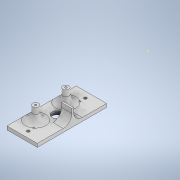
# Autodesk Inventor part: suport_steppper_part45_v2
Saved by Autodesk Inventor 2022.6 (Build 266554000, 554)
## iProperties
Created: 2026-10-28
Part Number: suport_steppper_part45_v2
Material: Generic
Document SubType Name: Modeling
Designer: Dragos Macovei
Density: 1 g/cm^3
Appearance: Default
Author: Dragos Macovei
Autodesk Inventor part; units mm, degrees
ref_plane "YZ Plane" through (0, 0, 0) normal (1, 0, 0) x (0, 1, 0)
ref_plane "XZ Plane" through (0, 0, 0) normal (0, 1, 0) x (-1, 0, 0)
ref_plane "XY Plane" through (0, 0, 0) normal (0, 0, 1) x (1, 0, 0)
sketch "Sketch1" plane through (0, 0, 0) normal (0, 1, 0) x (-1, 0, 0)
  circle A0 centre (-10.9929, 149.7887) radius 1.6
  circle A1 centre (-10.9929, 83.7887) radius 1.6
  line L0 (6.5071, 156.7887) -> (-28.4929, 156.7887)
  line L1 (-28.4929, 156.7887) -> (-28.4929, 76.7887)
  line L2 (-28.4929, 76.7887) -> (6.5071, 76.7887)
  line L3 (6.5071, 76.7887) -> (6.5071, 156.7887)
  point P0 (0, 0)
  point P1 (-10.9929, 156.7887)
  dimension "d0" = 66
  dimension "d1" = 17.5
  dimension "d2" = 35
  dimension "d3" = 17.5
  dimension "d4" = 3.2
  dimension "d5" = 3.2
  dimension "d6" = 80
  dimension "d7" = 7
  constraints: 8 end point, 2 centre point, 2 parallel, 1 horizontal, 1 midpoint, 1 perpendicular
  measures "d0" distance of A1.centre A0.centre
  measures "d1" distance from line of L3 A0.centre
  measures "d2" distance of L0.start L0.end
  measures "d3" distance from line of L3 A1.centre
  measures "d4" diameter of A0
  measures "d5" diameter of A1
  measures "d6" distance of L2.end L0.start
  measures "d7" distance of point (-10.993, 156.789) A0.centre
extrude "Extrusion1" add sketch "Sketch1" along normal blind 4
sketch "Sketch2" plane through (0, 4, 0) normal (0, 1, 0) x (1, 0, 0)
  line L0 (28.4929, -156.7887) -> (28.4929, -76.7887) projected
  line L1 (28.4929, -76.7887) -> (-6.5071, -76.7887) projected
  line L2 (-6.5071, -76.7887) -> (-6.5071, -156.7887) projected
  line L3 (-6.5071, -156.7887) -> (28.4929, -156.7887) projected
  circle A0 centre (10.9929, -149.7887) radius 1.6 projected
  circle A1 centre (10.9929, -83.7887) radius 1.6 projected
  circle A2 centre (3.9929, -134.2887) radius 1.15
  circle A3 centre (3.9929, -99.2887) radius 1.15
  line L4 (-6.5071, -76.7887) -> (-6.5071, -156.7887) projected
  line L5 (28.4929, -156.7887) -> (28.4929, -76.7887) projected
  line L6 (-6.5071, -116.7887) -> (28.4929, -116.7887)
  circle A4 centre (3.9929, -99.2887) radius 3.5
  circle A5 centre (10.9929, -149.7887) radius 1.6 projected
  line L7 (10.9929, -149.7887) -> (10.9929, -83.7887)
  circle A6 centre (3.9929, -134.2887) radius 3.5
  point P0 (0, 0)
  dimension "d10" = 35
  dimension "d11" = 17.5
  dimension "d13" = 7
  dimension "d14" = 2.3
  dimension "d15" = 2.3
  dimension "d28" = 7
  dimension "d29" = 7
  dimension "d30" = 7
  constraints: 4 centre point, 4 end point, 2 coincident, 2 midpoint, 1 perpendicular, 1 vertical
  measures "d10" distance of A2.centre A3.centre
  measures "d11" distance from line of L6 A2.centre
  measures "d13" diameter of A4
  measures "d14" diameter of A2
  measures "d15" diameter of A3
  measures "d28" distance from line of L7 A3.centre
  measures "d29" distance from line of L7 A2.centre
  measures "d30" diameter of A6
extrude "Extrusion2" add sketch "Sketch2" along normal blind 15 contours A4 | A6
fillet "Fillet1" radius 8 2 edges at (0.4929, 4, 99.2887) (0.4929, 4, 134.2887)
sketch "Sketch3" plane through (0, 4, 0) normal (0, 1, 0) x (1, 0, 0)
  line L0 (28.4929, -156.7887) -> (28.4929, -76.7887) projected
  line L1 (28.4929, -76.7887) -> (-6.5071, -76.7887) projected
  line L2 (-6.5071, -76.7887) -> (-6.5071, -94.5983) projected
  line L3 (-6.5071, -156.7887) -> (28.4929, -156.7887) projected
  circle A0 centre (10.9929, -149.7887) radius 1.6 projected
  circle A1 centre (10.9929, -83.7887) radius 1.6 projected
  arc A2 (-6.5071, -103.9791) -> (-6.5071, -94.5983) centre (3.9929, -99.2887) ccw projected
  circle A3 centre (10.9929, -116.7887) radius 5.5
  circle A4 centre (10.9929, -149.7887) radius 1.6 projected
  line L4 (10.9929, -149.7887) -> (10.9929, -83.7887)
  line L5 (-6.5071, -103.9791) -> (-6.5071, -129.5983) projected
  arc A5 (-6.5071, -138.9791) -> (-6.5071, -129.5983) centre (3.9929, -134.2887) ccw projected
  line L6 (-6.5071, -138.9791) -> (-6.5071, -156.7887) projected
  point P0 (0, 0)
  dimension "d19" = 11
  dimension "d20" = 33
  constraints: 2 end point, 1 centre point, 1 vertical
  measures "d19" diameter of A3
  measures "d20" distance of L4.end A3.centre
extrude "Extrusion3" cut sketch "Sketch3" against normal blind 15 contours L4 A3 | A3 L4
sketch "Sketch4" plane through (0, 4, 0) normal (0, 1, 0) x (1, 0, 0)
  circle A0 centre (10.9929, -116.7887) radius 5.5 projected
  line L0 (28.4929, -156.7887) -> (28.4929, -76.7887) projected
  line L1 (28.4929, -76.7887) -> (-6.5071, -76.7887) projected
  line L2 (-6.5071, -76.7887) -> (-6.5071, -94.5983) projected
  line L3 (-6.5071, -156.7887) -> (28.4929, -156.7887) projected
  circle A1 centre (10.9929, -149.7887) radius 1.6 projected
  circle A2 centre (10.9929, -83.7887) radius 1.6 projected
  arc A3 (-6.5071, -103.9791) -> (-6.5071, -94.5983) centre (3.9929, -99.2887) ccw projected
  circle A4 centre (10.9929, -116.7887) radius 5.5 projected
  line L4 (28.4929, -156.7887) -> (28.4929, -76.7887) projected
  line L5 (16.4929, -116.7887) -> (28.4929, -116.7887)
  line L6 (28.4929, -116.7887) -> (28.4929, -114.7887)
  line L7 (28.4929, -114.7887) -> (16.4929, -114.7887)
  line L8 (16.4929, -114.7887) -> (16.4929, -116.7887)
  line L9 (-6.5071, -103.9791) -> (-6.5071, -129.5983) projected
  arc A5 (-6.5071, -138.9791) -> (-6.5071, -129.5983) centre (3.9929, -134.2887) ccw projected
  line L10 (-6.5071, -138.9791) -> (-6.5071, -156.7887) projected
  point P0 (0, 0)
  dimension "d23" = 2
  constraints: 8 end point, 2 parallel, 1 horizontal, 1 horizontal alignment, 1 perpendicular, 1 point on line, 1 other
  measures "d23" distance of L6.end L5.end
extrude "Extrusion4" add sketch "Sketch4" along normal blind 15 contours L8 L7 L0 L5
fillet "Fillet2" radius 10 2 edges at (22.4929, 4, 116.7887) (22.4929, 4, 114.7887)
sketch "Sketch5" plane through (0, 4, 0) normal (0, 1, 0) x (1, 0, 0)
  point P0 (0, 0)
sketch "Sketch6" plane through (0, 4, 0) normal (0, 1, 0) x (1, 0, 0)
  line L0 (28.4929, -104.7887) -> (16.4929, -104.7887) projected
  line L1 (28.4929, -104.7887) -> (28.4929, -76.7887) projected
  line L2 (28.4929, -76.7887) -> (-6.5071, -76.7887) projected
  line L3 (-6.5071, -76.7887) -> (-6.5071, -94.5983) projected
  arc A0 (-6.5071, -103.9791) -> (-6.5071, -94.5983) centre (3.9929, -99.2887) ccw projected
  line L4 (-6.5071, -103.9791) -> (-6.5071, -129.5983) projected
  arc A1 (-6.5071, -138.9791) -> (-6.5071, -129.5983) centre (3.9929, -134.2887) ccw projected
  line L5 (-6.5071, -138.9791) -> (-6.5071, -156.7887) projected
  line L6 (-6.5071, -156.7887) -> (28.4929, -156.7887) projected
  line L7 (28.4929, -156.7887) -> (28.4929, -126.7887) projected
  line L8 (16.4929, -126.7887) -> (28.4929, -126.7887) projected
  line L9 (16.4929, -126.7887) -> (16.4929, -116.7887) projected
  circle A2 centre (10.9929, -116.7887) radius 5.5 projected
  line L10 (16.4929, -116.7887) -> (16.4929, -104.7887) projected
  circle A3 centre (10.9929, -149.7887) radius 1.6 projected
  circle A4 centre (10.9929, -83.7887) radius 1.6 projected
  line L11 (10.9929, -67.9055) -> (10.9929, -188.8412)
  arc A5 (-6.5071, -103.9791) -> (-6.5071, -94.5983) centre (3.9929, -99.2887) ccw projected
  circle A6 centre (10.9929, -90.1646) radius 0.8
  arc A7 (-6.5071, -138.9791) -> (-6.5071, -129.5983) centre (3.9929, -134.2887) ccw projected
  circle A8 centre (10.9929, -143.4129) radius 0.8
  point P0 (0, 0)
  dimension "d31" = 1.6
  dimension "d32" = 1.6
  constraints: 4 point on line, 2 centre point, 2 end point, 2 point on circle, 1 horizontal alignment, 1 vertical
  measures "d31" diameter of A6
  measures "d32" diameter of A8
extrude "Extrusion5" cut sketch "Sketch6" along normal through all both and the other way through all contours A6 L11 A0 | A0 L11 A6 | A6 A0 L11 | A8 L11 A1 | A1 L11 A8 | L11 A1 A8 | A6 L11 A0 | L11 A8 A1 picked at (11.0628, -90.4862) picked at (11.2713, -90.0532) picked at (10.7012, -90.2613) picked at (11.2713, -143.5242) picked at (11.0628, -143.0913) picked at (10.7012, -143.3162) picked at (10.9217, -89.8446) picked at (10.9217, -143.7328)
equation "\"d3\" = d1"
equation "\"d5\" = d4"
equation "\"d29\" = d28"
equation "\"d32\" = d31"
body "Solid1"
